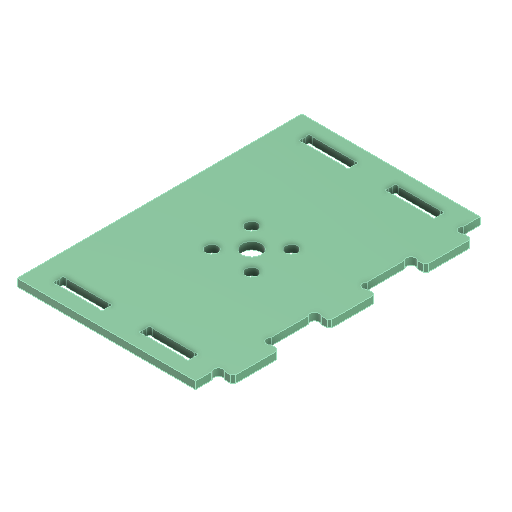
# Autodesk Inventor part: CUT_FR4_Waveguide_Top_Plate
Saved by Autodesk Inventor 2026.1 (Build 301233000, 233)
## iProperties
Created: 2025-11-04
Part Number: CUT_FR4_Waveguide_Top_Plate
Material: Generic
Document SubType Name: Modeling
Designer: User
Density: 1 g/cm^3
Appearance: Smooth - Dark Sea Green
Author: User
Autodesk Inventor part; units mm, degrees
ref_plane "YZ Plane" through (0, 0, 0) normal (1, 0, 0) x (0, 1, 0)
ref_plane "XZ Plane" through (0, 0, 0) normal (0, 1, 0) x (-1, 0, 0)
ref_plane "XY Plane" through (0, 0, 0) normal (0, 0, 1) x (1, 0, 0)
sketch "Sketch1" plane through (0, 0, 0) normal (0, 1, 0) x (-1, 0, 0)
  line L0 (19.35, 25.9) -> (-19.35, 25.9)
  line L1 (-19.35, 25.9) -> (-19.35, -25.9)
  line L2 (-19.35, -25.9) -> (19.35, -25.9)
  line L3 (19.35, -25.9) -> (19.35, 25.9)
  line L4 (-24.35, 30.9) -> (24.35, 30.9)
  line L5 (24.35, 30.9) -> (24.35, -30.9)
  line L6 (24.35, -30.9) -> (-24.35, -30.9)
  line L7 (-24.35, -30.9) -> (-24.35, 30.9)
  line L8 (19.35, 25.9) -> (19.35, 30.9)
  line L9 (19.35, -25.9) -> (19.35, -30.9)
  line L10 (-19.35, 25.9) -> (-19.35, 30.9)
  line L11 (-19.35, -25.9) -> (-19.35, -30.9)
  point P0 (0, 0)
  dimension "d0" = 38.7
  dimension "d1" = 51.8
  dimension "d2" = 19.35
  dimension "d3" = 25.9
  dimension "d4" = 5
  constraints: 24 end point, 6 point on line, 4 parallel, 4 perpendicular, 1 horizontal, 3 other
  measures "d0" distance of L1.end L2.end
  measures "d1" distance of L0.end L1.end
  measures "d2" distance from line of L1 point (0, 0)
  measures "d3" distance from line of L0 point (0, 0)
  measures "d4" distance between parallel lines of L0 L4
extrude "Extrusion1" add sketch "Sketch1" along normal blind 1.6 contours L3 L2 L1 L0 | L0 L10 L4 L8 | L9 L6 L11 L2
sketch "Sketch2" plane through (0, 1.6, 0) normal (0, 1, 0) x (1, 0, 0)
  line L0 (-4.35, 27.5) -> (-14.35, 27.5) construction
  line L1 (-14.35, 27.5) -> (-14.35, 25.9) construction
  line L2 (-14.35, 25.9) -> (-4.35, 25.9) construction
  line L3 (-4.35, 25.9) -> (-4.35, 27.5) construction
  line L4 (-4.1, 27.75) -> (-14.6, 27.75)
  line L5 (-14.6, 27.75) -> (-14.6, 25.65)
  line L6 (-14.6, 25.65) -> (-4.1, 25.65)
  line L7 (-4.1, 25.65) -> (-4.1, 27.75)
  line L8 (14.35, 27.5) -> (4.35, 27.5) construction
  line L9 (4.35, 27.5) -> (4.35, 25.9) construction
  line L10 (4.35, 25.9) -> (14.35, 25.9) construction
  line L11 (14.35, 25.9) -> (14.35, 27.5) construction
  line L12 (14.6, 27.75) -> (4.1, 27.75)
  line L13 (4.1, 27.75) -> (4.1, 25.65)
  line L14 (4.1, 25.65) -> (14.6, 25.65)
  line L15 (14.6, 25.65) -> (14.6, 27.75)
  dimension "d7" = 0.25
  dimension "d8" = 0.25
  constraints: 16 end point, 6 other
  measures "d7" distance between parallel lines of L4 L0
  measures "d8" distance between parallel lines of L12 L8
extrude "Extrusion2" cut sketch "Sketch2" against normal up to next
sketch "Sketch3" plane through (0, 1.6, 0) normal (0, 1, 0) x (1, 0, 0)
  circle A0 centre (-4.4536, 26.0036) radius 0.5
  circle A1 centre (-14.2464, 26.0036) radius 0.5
  circle A2 centre (-14.2464, 27.3964) radius 0.5
  circle A3 centre (-4.4536, 27.3964) radius 0.5
  circle A4 centre (14.2464, 26.0036) radius 0.5
  circle A5 centre (4.4536, 26.0036) radius 0.5
  circle A6 centre (4.4536, 27.3964) radius 0.5
  circle A7 centre (14.2464, 27.3964) radius 0.5
  point P0 (-4.1, 27.75)
  point P1 (-14.6, 25.65)
  point P2 (-4.1, 25.65)
  point P3 (-14.6, 27.75)
  point P4 (14.6, 27.75)
  point P5 (4.1, 25.65)
  point P6 (14.6, 25.65)
  point P7 (4.1, 27.75)
  dimension "d11" = 45
  dimension "d12" = 0.5
  dimension "d13" = 1
  dimension "d14" = 45
  dimension "d15" = 0.5
  dimension "d16" = 1
  dimension "d17" = 45
  dimension "d18" = 0.5
  dimension "d19" = 1
  dimension "d20" = 45
  dimension "d21" = 0.5
  dimension "d22" = 1
  dimension "d23" = 45
  dimension "d24" = 0.5
  dimension "d25" = 1
  dimension "d26" = 45
  dimension "d27" = 0.5
  dimension "d28" = 1
  dimension "d29" = 45
  dimension "d30" = 0.5
  dimension "d31" = 1
  dimension "d32" = 45
  dimension "d33" = 0.5
  dimension "d34" = 1
  constraints: 8 centre point
  measures "d12" distance of A0.centre point (-4.1, 25.65)
  measures "d13" diameter of A0
  measures "d15" distance of A1.centre point (-14.6, 25.65)
  measures "d16" diameter of A1
  measures "d18" distance of A2.centre point (-14.6, 27.75)
  measures "d19" diameter of A2
  measures "d21" distance of A3.centre point (-4.1, 27.75)
  measures "d22" diameter of A3
  measures "d24" distance of A4.centre point (14.6, 25.65)
  measures "d25" diameter of A4
  measures "d27" distance of A5.centre point (4.1, 25.65)
  measures "d28" diameter of A5
  measures "d30" distance of A6.centre point (4.1, 27.75)
  measures "d31" diameter of A6
  measures "d33" distance of A7.centre point (14.6, 27.75)
  measures "d34" diameter of A7
extrude "Extrusion3" cut sketch "Sketch3" against normal up to surface (1.6 mm away)
sketch "Sketch4" plane through (0, 1.6, 0) normal (0, 1, 0) x (1, 0, 0)
  line L0 (14.35, -25.9) -> (4.35, -25.9) construction
  line L1 (4.35, -25.9) -> (4.35, -27.5) construction
  line L2 (4.35, -27.5) -> (14.35, -27.5) construction
  line L3 (14.35, -27.5) -> (14.35, -25.9) construction
  line L4 (14.6, -25.65) -> (4.1, -25.65)
  line L5 (4.1, -25.65) -> (4.1, -27.75)
  line L6 (4.1, -27.75) -> (14.6, -27.75)
  line L7 (14.6, -27.75) -> (14.6, -25.65)
  line L8 (-4.35, -25.9) -> (-14.35, -25.9) construction
  line L9 (-14.35, -25.9) -> (-14.35, -27.5) construction
  line L10 (-14.35, -27.5) -> (-4.35, -27.5) construction
  line L11 (-4.35, -27.5) -> (-4.35, -25.9) construction
  line L12 (-4.1, -25.65) -> (-14.6, -25.65)
  line L13 (-14.6, -25.65) -> (-14.6, -27.75)
  line L14 (-14.6, -27.75) -> (-4.1, -27.75)
  line L15 (-4.1, -27.75) -> (-4.1, -25.65)
  dimension "d37" = 0.25
  dimension "d38" = 0.25
  constraints: 16 end point, 6 other
  measures "d37" distance between parallel lines of L4 L0
  measures "d38" distance between parallel lines of L12 L8
extrude "Extrusion4" cut sketch "Sketch4" against normal up to next
sketch "Sketch5" plane through (0, 1.6, 0) normal (0, 1, 0) x (1, 0, 0)
  circle A0 centre (14.2464, -27.3964) radius 0.5
  circle A1 centre (4.4536, -27.3964) radius 0.5
  circle A2 centre (4.4536, -26.0036) radius 0.5
  circle A3 centre (14.2464, -26.0036) radius 0.5
  circle A4 centre (-4.4536, -27.3964) radius 0.5
  circle A5 centre (-14.2464, -27.3964) radius 0.5
  circle A6 centre (-14.2464, -26.0036) radius 0.5
  circle A7 centre (-4.4536, -26.0036) radius 0.5
  point P0 (14.6, -25.65)
  point P1 (4.1, -27.75)
  point P2 (14.6, -27.75)
  point P3 (4.1, -25.65)
  point P4 (-4.1, -25.65)
  point P5 (-14.6, -27.75)
  point P6 (-4.1, -27.75)
  point P7 (-14.6, -25.65)
  dimension "d41" = 45
  dimension "d42" = 0.5
  dimension "d43" = 1
  dimension "d44" = 45
  dimension "d45" = 0.5
  dimension "d46" = 1
  dimension "d47" = 45
  dimension "d48" = 0.5
  dimension "d49" = 1
  dimension "d50" = 45
  dimension "d51" = 0.5
  dimension "d52" = 1
  dimension "d53" = 45
  dimension "d54" = 0.5
  dimension "d55" = 1
  dimension "d56" = 45
  dimension "d57" = 0.5
  dimension "d58" = 1
  dimension "d59" = 45
  dimension "d60" = 0.5
  dimension "d61" = 1
  dimension "d62" = 45
  dimension "d63" = 0.5
  dimension "d64" = 1
  constraints: 8 centre point
  measures "d42" distance of A0.centre point (14.6, -27.75)
  measures "d43" diameter of A0
  measures "d45" distance of A1.centre point (4.1, -27.75)
  measures "d46" diameter of A1
  measures "d48" distance of A2.centre point (4.1, -25.65)
  measures "d49" diameter of A2
  measures "d51" distance of A3.centre point (14.6, -25.65)
  measures "d52" diameter of A3
  measures "d54" distance of A4.centre point (-4.1, -27.75)
  measures "d55" diameter of A4
  measures "d57" distance of A5.centre point (-14.6, -27.75)
  measures "d58" diameter of A5
  measures "d60" distance of A6.centre point (-14.6, -25.65)
  measures "d61" diameter of A6
  measures "d63" distance of A7.centre point (-4.1, -25.65)
  measures "d64" diameter of A7
extrude "Extrusion5" cut sketch "Sketch5" against normal up to surface (1.6 mm away)
sketch "Sketch6" plane through (19.35, 0, 30.9) normal (1, 0, 0) x (0, 0, -1)
  line L0 (0, 0) -> (61.8, 0) construction
  line L1 (0, 1.6) -> (61.8, 1.6) construction
  line L2 (5, 0) -> (15, 0)
  line L3 (15, 0) -> (15, 1.6)
  line L4 (15, 1.6) -> (5, 1.6)
  line L5 (5, 1.6) -> (5, 0)
  dimension "d67" = 5
  dimension "d68" = 10
  constraints: 8 end point, 2 collinear, 2 parallel, 1 perpendicular
  measures "d67" distance from line of L5 L0.start
  measures "d68" distance between parallel lines of L3 L5
sketch "Sketch7" plane through (19.35, 0, 30.9) normal (1, 0, 0) x (0, 0, -1)
  line L0 (0, 0) -> (61.8, 0) projected
extrude "Extrusion6" add sketch "Sketch6" along normal blind 3.2
pattern_linear "Rectangular Pattern1" count 3 spacing 20.9 along (0, 0, -1) of "Extrusion6"
sketch "Sketch8" plane through (0, 0, 0) normal (0, -1, 0) x (1, 0, 0)
  line L0 (19.35, 30.9) -> (19.35, 25.9) construction
  line L1 (19.35, 25.9) -> (22.55, 25.9) construction
  circle A0 centre (20.0571, 26.6071) radius 1
  line L2 (19.35, 15.9) -> (19.35, 5) construction
  line L3 (19.35, 15.9) -> (22.55, 15.9) construction
  circle A1 centre (20.0571, 15.1929) radius 1
  line L4 (19.35, -5) -> (19.35, -15.9) construction
  line L5 (19.35, -15.9) -> (22.55, -15.9) construction
  circle A2 centre (20.0571, -15.1929) radius 1
  line L6 (19.35, -25.9) -> (19.35, -30.9) construction
  line L7 (19.35, -25.9) -> (22.55, -25.9) construction
  circle A3 centre (20.0571, -26.6071) radius 1
  line L8 (19.35, 5) -> (22.55, 5) construction
  circle A4 centre (20.0571, 5.7071) radius 1
  line L9 (19.35, -5) -> (22.55, -5) construction
  circle A5 centre (20.0571, -5.7071) radius 1
  dimension "d75" = 2
  dimension "d77" = 2
  dimension "d79" = 2
  dimension "d81" = 2
  dimension "d83" = 2
  dimension "d85" = 2
  dimension "d74" = 45
  dimension "d76" = 45
  dimension "d78" = 45
  dimension "d80" = 45
  dimension "d82" = 45
  dimension "d84" = 45
  constraints: 6 coincident, 18 other
extrude "Extrusion7" cut sketch "Sketch8" against normal up to surface (1.6 mm away)
chamfer "Chamfer1" distance 0.5 angle 45 6 edges at (22.55, 0.8, 15.9) (22.55, 0.8, 25.9) (22.55, 0.8, -5) (22.55, 0.8, 5) (22.55, 0.8, -25.9) (22.55, 0.8, -15.9)
sketch "Sketch9" plane through (0, 1.6, 0) normal (0, 1, 0) x (1, 0, 0)
  line L0 (22.55, 16.4) -> (22.05, 15.9) projected
  line L1 (22.55, 25.4) -> (22.55, 16.4) projected
  line L2 (22.05, 25.9) -> (22.55, 25.4) projected
  line L3 (20.7642, 25.9) -> (22.05, 25.9) projected
  arc A0 (19.35, 27.3142) -> (20.7642, 25.9) centre (20.0571, 26.6071) ccw projected
  line L4 (19.35, 27.3142) -> (19.35, 30.9) projected
  line L5 (19.35, 30.9) -> (-19.35, 30.9) projected
  line L6 (-19.35, 30.9) -> (-19.35, -30.9) projected
  line L7 (-19.35, -30.9) -> (19.35, -30.9) projected
  line L8 (19.35, -30.9) -> (19.35, -27.3142) projected
  arc A1 (20.7642, -25.9) -> (19.35, -27.3142) centre (20.0571, -26.6071) ccw projected
  line L9 (20.7642, -25.9) -> (22.05, -25.9) projected
  line L10 (22.55, -25.4) -> (22.05, -25.9) projected
  line L11 (22.55, -16.4) -> (22.55, -25.4) projected
  line L12 (22.05, -15.9) -> (22.55, -16.4) projected
  line L13 (20.7642, -15.9) -> (22.05, -15.9) projected
  arc A2 (19.35, -14.4858) -> (20.7642, -15.9) centre (20.0571, -15.1929) ccw projected
  line L14 (19.35, -14.4858) -> (19.35, -6.4142) projected
  arc A3 (20.7642, -5) -> (19.35, -6.4142) centre (20.0571, -5.7071) ccw projected
  line L15 (20.7642, -5) -> (22.05, -5) projected
  line L16 (22.55, -4.5) -> (22.05, -5) projected
  line L17 (22.55, 4.5) -> (22.55, -4.5) projected
  line L18 (22.05, 5) -> (22.55, 4.5) projected
  line L19 (20.7642, 5) -> (22.05, 5) projected
  arc A4 (19.35, 6.4142) -> (20.7642, 5) centre (20.0571, 5.7071) ccw projected
  line L20 (19.35, 6.4142) -> (19.35, 14.4858) projected
  arc A5 (20.7642, 15.9) -> (19.35, 14.4858) centre (20.0571, 15.1929) ccw projected
  line L21 (20.7642, 15.9) -> (22.05, 15.9) projected
  arc A6 (4.8071, 27.75) -> (4.1, 27.0429) centre (4.4536, 27.3964) ccw projected
  line L22 (4.8071, 27.75) -> (13.8929, 27.75) projected
  arc A7 (14.6, 27.0429) -> (13.8929, 27.75) centre (14.2464, 27.3964) ccw projected
  line L23 (14.6, 27.0429) -> (14.6, 26.3571) projected
  arc A8 (13.8929, 25.65) -> (14.6, 26.3571) centre (14.2464, 26.0036) ccw projected
  line L24 (13.8929, 25.65) -> (4.8071, 25.65) projected
  arc A9 (4.1, 26.3571) -> (4.8071, 25.65) centre (4.4536, 26.0036) ccw projected
  line L25 (4.1, 26.3571) -> (4.1, 27.0429) projected
  arc A10 (-4.1, 27.0429) -> (-4.8071, 27.75) centre (-4.4536, 27.3964) ccw projected
  line L26 (-4.1, 27.0429) -> (-4.1, 26.3571) projected
  arc A11 (-4.8071, 25.65) -> (-4.1, 26.3571) centre (-4.4536, 26.0036) ccw projected
  line L27 (-4.8071, 25.65) -> (-13.8929, 25.65) projected
  arc A12 (-14.6, 26.3571) -> (-13.8929, 25.65) centre (-14.2464, 26.0036) ccw projected
  line L28 (-14.6, 26.3571) -> (-14.6, 27.0429) projected
  arc A13 (-13.8929, 27.75) -> (-14.6, 27.0429) centre (-14.2464, 27.3964) ccw projected
  line L29 (-13.8929, 27.75) -> (-4.8071, 27.75) projected
  arc A14 (14.6, -26.3571) -> (13.8929, -25.65) centre (14.2464, -26.0036) ccw projected
  line L30 (14.6, -26.3571) -> (14.6, -27.0429) projected
  arc A15 (13.8929, -27.75) -> (14.6, -27.0429) centre (14.2464, -27.3964) ccw projected
  line L31 (13.8929, -27.75) -> (4.8071, -27.75) projected
  arc A16 (4.1, -27.0429) -> (4.8071, -27.75) centre (4.4536, -27.3964) ccw projected
  line L32 (4.1, -27.0429) -> (4.1, -26.3571) projected
  arc A17 (4.8071, -25.65) -> (4.1, -26.3571) centre (4.4536, -26.0036) ccw projected
  line L33 (4.8071, -25.65) -> (13.8929, -25.65) projected
  arc A18 (-13.8929, -25.65) -> (-14.6, -26.3571) centre (-14.2464, -26.0036) ccw projected
  line L34 (-13.8929, -25.65) -> (-4.8071, -25.65) projected
  arc A19 (-4.1, -26.3571) -> (-4.8071, -25.65) centre (-4.4536, -26.0036) ccw projected
  line L35 (-4.1, -26.3571) -> (-4.1, -27.0429) projected
  arc A20 (-4.8071, -27.75) -> (-4.1, -27.0429) centre (-4.4536, -27.3964) ccw projected
  line L36 (-4.8071, -27.75) -> (-13.8929, -27.75) projected
  arc A21 (-14.6, -27.0429) -> (-13.8929, -27.75) centre (-14.2464, -27.3964) ccw projected
  line L37 (-14.6, -27.0429) -> (-14.6, -26.3571) projected
  circle A22 centre (0.65, 0) radius 2.1
  circle A23 centre (-3.67, 4.32) radius 1.3
  circle A24 centre (-3.67, -4.32) radius 1.3
  circle A25 centre (4.97, -4.32) radius 1.3
  circle A26 centre (4.97, 4.32) radius 1.3
  point P0 (0, 0)
  dimension "d91" = 4.2
  dimension "d92" = 2.6
  dimension "d93" = 2.6
  dimension "d94" = 2.6
  dimension "d95" = 2.6
  dimension "d96" = 4.32
  dimension "d97" = 4.32
  dimension "d98" = 4.32
  dimension "d99" = 4.32
  dimension "d100" = 20
  constraints: 5 centre point, 2 horizontal alignment, 2 vertical alignment
  measures "d91" diameter of A22
  measures "d92" diameter of A23
  measures "d93" diameter of A24
  measures "d94" diameter of A25
  measures "d95" diameter of A26
  measures "d96" horizontal distance of A22.centre A23.centre
  measures "d97" horizontal distance of A24.centre A22.centre
  measures "d98" horizontal distance of A22.centre A23.centre
  measures "d99" horizontal distance of A22.centre A26.centre
  measures "d100" distance from line of L6 A22.centre
extrude "Extrusion8" cut sketch "Sketch9" against normal blind 10 contours A22 | A23 | A24 | A25 | A26
equation "\"d2\" = 0.5 * d0"
equation "\"d3\" = 0.5 * d1"
equation "\"d92\" = d95"
equation "\"d93\" = d95"
equation "\"d94\" = d95"
equation "\"d97\" = d96"
equation "\"d98\" = d96"
equation "\"d99\" = d98"
body "Solid1"
